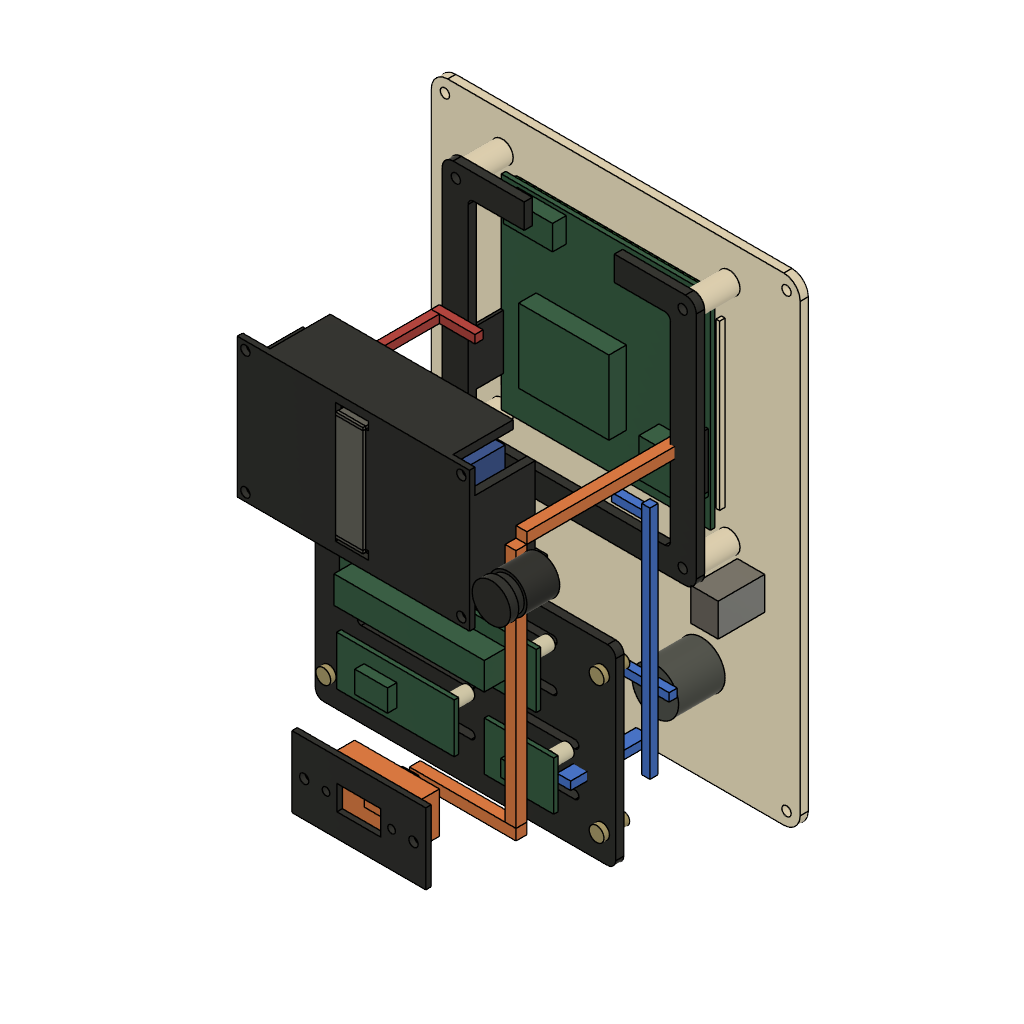
ORBIT-RevD-inspection (Autodesk Fusion 360 design; units mm, degrees)
part number: 2026-10-11-19-51-13-014
part number: 2026-10-11-19-51-13-171
part number: 2026-10-11-19-51-13-754
part number: 2026-10-11-19-51-15-998
part number: 2026-10-11-19-51-20-157
part number: 2026-10-11-19-51-22-045
part number: 2026-10-11-19-51-29-710
part number: 2026-10-11-19-51-37-269
part number: 2026-10-11-19-51-38-093
part number: 2026-10-11-19-51-39-125
part number: 2026-10-11-19-51-40-164
part number: 2026-10-11-19-51-41-218
part number: 2026-10-11-19-51-42-298
part number: 2026-10-11-19-51-44-407
part number: 2026-10-11-19-51-45-579
part number: 2026-10-11-19-51-46-216
part number: 2026-10-11-19-51-46-876
part number: 2026-10-11-19-51-47-517
part number: 2026-10-11-19-51-48-186
part number: 2026-10-11-19-51-49-445
part number: 2026-10-11-19-51-50-730
part number: 2026-10-11-19-51-51-999
part number: 2026-10-11-19-51-55-690
part number: 2026-10-11-19-52-03-764
part number: 2026-10-11-19-52-06-742
part number: 2026-10-11-19-52-09-801
part number: 2026-10-11-19-54-35-240
part number: 2026-10-11-20-27-58-250
part number: 2026-10-11-20-28-22-138
part number: 2026-10-11-20-28-23-770
part number: 2026-10-11-20-28-28-011
part number: 2026-10-11-20-28-32-254
Autodesk Fusion 360 part; units mm, degrees
(part 1 of 2)
ref_plane "WorkPlane1" through (0, 0, 0) normal (0, 0, 1) x (1, 0, 0) in component "01 Ivory front panel"
sketch "Front panel 3mm" plane through (0, 0, 0) normal (0, 0, 1) x (1, 0, 0) in component "01 Ivory front panel"
  line L0 (6, 0) -> (129, 0)
  arc A0 (129, 0) -> (135, 6) centre (129, 6) ccw
  line L1 (135, 6) -> (135, 169)
  arc A1 (135, 169) -> (129, 175) centre (129, 169) ccw
  line L2 (129, 175) -> (6, 175)
  arc A2 (6, 175) -> (0, 169) centre (6, 169) ccw
  line L3 (0, 169) -> (0, 6)
  arc A3 (0, 6) -> (6, 0) centre (6, 6) ccw
extrude "Front panel 3mm (1)" add sketch "Front panel 3mm" along normal blind 3 makes body 1 in component "01 Ivory front panel"
ref_plane "WorkPlane2" through (0, 0, 0) normal (0, 0, 1) x (1, 0, 0) in component "01 Ivory front panel"
sketch "Display aperture - provisional" plane through (0, 0, 0) normal (0, 0, 1) x (1, 0, 0) in component "01 Ivory front panel"
  line L0 (32.5, 85) -> (102.5, 85)
  arc A0 (102.5, 85) -> (103.5, 86) centre (102.5, 86) ccw
  line L1 (103.5, 86) -> (103.5, 156)
  arc A1 (103.5, 156) -> (102.5, 157) centre (102.5, 156) ccw
  line L2 (102.5, 157) -> (32.5, 157)
  arc A2 (32.5, 157) -> (31.5, 156) centre (32.5, 156) ccw
  line L3 (31.5, 156) -> (31.5, 86)
  arc A3 (31.5, 86) -> (32.5, 85) centre (32.5, 86) ccw
extrude "Display aperture - provisional (1)" cut sketch "Display aperture - provisional" along normal blind 3 bodies 1 in component "01 Ivory front panel"
ref_plane "WorkPlane3" through (0, 0, 0) normal (0, 0, 1) x (1, 0, 0) in component "01 Ivory front panel"
sketch "Encoder clearance" plane through (0, 0, 0) normal (0, 0, 1) x (1, 0, 0) in component "01 Ivory front panel"
  circle A0 centre (36, 36) radius 3.7
extrude "Encoder clearance (1)" cut sketch "Encoder clearance" along normal blind 3 bodies 1 in component "01 Ivory front panel"
ref_plane "WorkPlane4" through (0, 0, 0) normal (0, 0, 1) x (1, 0, 0) in component "01 Ivory front panel"
sketch "Potentiometer clearance" plane through (0, 0, 0) normal (0, 0, 1) x (1, 0, 0) in component "01 Ivory front panel"
  circle A0 centre (99, 36) radius 3.7
extrude "Potentiometer clearance (1)" cut sketch "Potentiometer clearance" along normal blind 3 bodies 1 in component "01 Ivory front panel"
ref_plane "WorkPlane5" through (0, 0, 0) normal (0, 0, 1) x (1, 0, 0) in component "01 Ivory front panel"
sketch "Hold toggle clearance" plane through (0, 0, 0) normal (0, 0, 1) x (1, 0, 0) in component "01 Ivory front panel"
  circle A0 centre (18, 70) radius 3.2
extrude "Hold toggle clearance (1)" cut sketch "Hold toggle clearance" along normal blind 3 bodies 1 in component "01 Ivory front panel"
ref_plane "WorkPlane6" through (0, 0, 0) normal (0, 0, 1) x (1, 0, 0) in component "01 Ivory front panel"
sketch "Grid toggle clearance" plane through (0, 0, 0) normal (0, 0, 1) x (1, 0, 0) in component "01 Ivory front panel"
  circle A0 centre (117, 70) radius 3.2
extrude "Grid toggle clearance (1)" cut sketch "Grid toggle clearance" along normal blind 3 bodies 1 in component "01 Ivory front panel"
ref_plane "WorkPlane7" through (0, 0, 0) normal (0, 0, 1) x (1, 0, 0) in component "01 Ivory front panel"
sketch "Decorative disk slot recess" plane through (0, 0, 0) normal (0, 0, 1) x (1, 0, 0) in component "01 Ivory front panel"
  line L0 (51.5, 16) -> (83.5, 16)
  arc A0 (83.5, 16) -> (84.5, 17) centre (83.5, 17) ccw
  line L1 (84.5, 17) -> (84.5, 17.4)
  arc A1 (84.5, 17.4) -> (83.5, 18.4) centre (83.5, 17.4) ccw
  line L2 (83.5, 18.4) -> (51.5, 18.4)
  arc A2 (51.5, 18.4) -> (50.5, 17.4) centre (51.5, 17.4) ccw
  line L3 (50.5, 17.4) -> (50.5, 17)
  arc A3 (50.5, 17) -> (51.5, 16) centre (51.5, 17) ccw
extrude "Decorative disk slot recess (1)" cut sketch "Decorative disk slot recess" along normal blind 0.8 bodies 1 in component "01 Ivory front panel"
ref_plane "WorkPlane8" through (0, 0, 0) normal (0, 0, 1) x (1, 0, 0) in component "01 Ivory front panel"
sketch "M3 front screw" plane through (0, 0, 0) normal (0, 0, 1) x (1, 0, 0) in component "01 Ivory front panel"
  circle A0 centre (5, 5) radius 1.7
extrude "M3 front screw (1)" cut sketch "M3 front screw" along normal blind 3 bodies 1 in component "01 Ivory front panel"
ref_plane "WorkPlane9" through (0, 0, 0) normal (0, 0, 1) x (1, 0, 0) in component "01 Ivory front panel"
sketch "M3 front screw (1)" plane through (0, 0, 0) normal (0, 0, 1) x (1, 0, 0) in component "01 Ivory front panel"
  circle A0 centre (130, 5) radius 1.7
extrude "M3 front screw (2)" cut sketch "M3 front screw (1)" along normal blind 3 bodies 1 in component "01 Ivory front panel"
ref_plane "WorkPlane10" through (0, 0, 0) normal (0, 0, 1) x (1, 0, 0) in component "01 Ivory front panel"
sketch "M3 front screw (2)" plane through (0, 0, 0) normal (0, 0, 1) x (1, 0, 0) in component "01 Ivory front panel"
  circle A0 centre (5, 170) radius 1.7
extrude "M3 front screw (3)" cut sketch "M3 front screw (2)" along normal blind 3 bodies 1 in component "01 Ivory front panel"
ref_plane "WorkPlane11" through (0, 0, 0) normal (0, 0, 1) x (1, 0, 0) in component "01 Ivory front panel"
sketch "M3 front screw (3)" plane through (0, 0, 0) normal (0, 0, 1) x (1, 0, 0) in component "01 Ivory front panel"
  circle A0 centre (130, 170) radius 1.7
extrude "M3 front screw (4)" cut sketch "M3 front screw (3)" along normal blind 3 bodies 1 in component "01 Ivory front panel"
ref_plane "WorkPlane1" through (0, 0, 3) normal (0, 0, 1) x (1, 0, 0) in component "02 Ivory shell"
sketch "Shell exterior" plane through (0, 0, 3) normal (0, 0, 1) x (1, 0, 0) in component "02 Ivory shell"
  line L0 (6, 0) -> (129, 0)
  arc A0 (129, 0) -> (135, 6) centre (129, 6) ccw
  line L1 (135, 6) -> (135, 169)
  arc A1 (135, 169) -> (129, 175) centre (129, 169) ccw
  line L2 (129, 175) -> (6, 175)
  arc A2 (6, 175) -> (0, 169) centre (6, 169) ccw
  line L3 (0, 169) -> (0, 6)
  arc A3 (0, 6) -> (6, 0) centre (6, 6) ccw
extrude "Shell exterior (1)" add sketch "Shell exterior" along normal blind 89 separate body makes body 2 in component "02 Ivory shell"
ref_plane "WorkPlane2" through (0, 0, 3) normal (0, 0, 1) x (1, 0, 0) in component "02 Ivory shell"
sketch "Open cavity 2.4mm walls" plane through (0, 0, 3) normal (0, 0, 1) x (1, 0, 0) in component "02 Ivory shell"
  line L0 (6, 2.4) -> (129, 2.4)
  arc A0 (129, 2.4) -> (132.6, 6) centre (129, 6) ccw
  line L1 (132.6, 6) -> (132.6, 169)
  arc A1 (132.6, 169) -> (129, 172.6) centre (129, 169) ccw
  line L2 (129, 172.6) -> (6, 172.6)
  arc A2 (6, 172.6) -> (2.4, 169) centre (6, 169) ccw
  line L3 (2.4, 169) -> (2.4, 6)
  arc A3 (2.4, 6) -> (6, 2.4) centre (6, 6) ccw
extrude "Open cavity 2.4mm walls (1)" cut sketch "Open cavity 2.4mm walls" along normal blind 89 bodies 2 in component "02 Ivory shell"
ref_plane "WorkPlane3" through (0, 0, 3) normal (0, 0, 1) x (1, 0, 0) in component "02 Ivory shell"
sketch "M3 corner boss" plane through (0, 0, 3) normal (0, 0, 1) x (1, 0, 0) in component "02 Ivory shell"
  circle A0 centre (5, 5) radius 4
extrude "M3 corner boss (1)" add sketch "M3 corner boss" along normal blind 8 bodies 2 in component "02 Ivory shell"
ref_plane "WorkPlane4" through (0, 0, 3) normal (0, 0, 1) x (1, 0, 0) in component "02 Ivory shell"
sketch "M3 boss bore" plane through (0, 0, 3) normal (0, 0, 1) x (1, 0, 0) in component "02 Ivory shell"
  circle A0 centre (5, 5) radius 1.7
extrude "M3 boss bore (1)" cut sketch "M3 boss bore" along normal blind 8 bodies 2 in component "02 Ivory shell"
ref_plane "WorkPlane5" through (0, 0, 84) normal (0, 0, 1) x (1, 0, 0) in component "02 Ivory shell"
sketch "M3 corner boss (1)" plane through (0, 0, 84) normal (0, 0, 1) x (1, 0, 0) in component "02 Ivory shell"
  circle A0 centre (5, 5) radius 4
extrude "M3 corner boss (2)" add sketch "M3 corner boss (1)" along normal blind 8 bodies 2 in component "02 Ivory shell"
ref_plane "WorkPlane6" through (0, 0, 84) normal (0, 0, 1) x (1, 0, 0) in component "02 Ivory shell"
sketch "M3 boss bore (1)" plane through (0, 0, 84) normal (0, 0, 1) x (1, 0, 0) in component "02 Ivory shell"
  circle A0 centre (5, 5) radius 1.7
extrude "M3 boss bore (2)" cut sketch "M3 boss bore (1)" along normal blind 8 bodies 2 in component "02 Ivory shell"
ref_plane "WorkPlane7" through (0, 0, 3) normal (0, 0, 1) x (1, 0, 0) in component "02 Ivory shell"
sketch "M3 corner boss (2)" plane through (0, 0, 3) normal (0, 0, 1) x (1, 0, 0) in component "02 Ivory shell"
  circle A0 centre (130, 5) radius 4
extrude "M3 corner boss (3)" add sketch "M3 corner boss (2)" along normal blind 8 bodies 2 in component "02 Ivory shell"
ref_plane "WorkPlane8" through (0, 0, 3) normal (0, 0, 1) x (1, 0, 0) in component "02 Ivory shell"
sketch "M3 boss bore (2)" plane through (0, 0, 3) normal (0, 0, 1) x (1, 0, 0) in component "02 Ivory shell"
  circle A0 centre (130, 5) radius 1.7
extrude "M3 boss bore (3)" cut sketch "M3 boss bore (2)" along normal blind 8 bodies 2 in component "02 Ivory shell"
ref_plane "WorkPlane9" through (0, 0, 84) normal (0, 0, 1) x (1, 0, 0) in component "02 Ivory shell"
sketch "M3 corner boss (3)" plane through (0, 0, 84) normal (0, 0, 1) x (1, 0, 0) in component "02 Ivory shell"
  circle A0 centre (130, 5) radius 4
extrude "M3 corner boss (4)" add sketch "M3 corner boss (3)" along normal blind 8 bodies 2 in component "02 Ivory shell"
ref_plane "WorkPlane10" through (0, 0, 84) normal (0, 0, 1) x (1, 0, 0) in component "02 Ivory shell"
sketch "M3 boss bore (3)" plane through (0, 0, 84) normal (0, 0, 1) x (1, 0, 0) in component "02 Ivory shell"
  circle A0 centre (130, 5) radius 1.7
extrude "M3 boss bore (4)" cut sketch "M3 boss bore (3)" along normal blind 8 bodies 2 in component "02 Ivory shell"
ref_plane "WorkPlane11" through (0, 0, 3) normal (0, 0, 1) x (1, 0, 0) in component "02 Ivory shell"
sketch "M3 corner boss (4)" plane through (0, 0, 3) normal (0, 0, 1) x (1, 0, 0) in component "02 Ivory shell"
  circle A0 centre (5, 170) radius 4
extrude "M3 corner boss (5)" add sketch "M3 corner boss (4)" along normal blind 8 bodies 2 in component "02 Ivory shell"
ref_plane "WorkPlane12" through (0, 0, 3) normal (0, 0, 1) x (1, 0, 0) in component "02 Ivory shell"
sketch "M3 boss bore (4)" plane through (0, 0, 3) normal (0, 0, 1) x (1, 0, 0) in component "02 Ivory shell"
  circle A0 centre (5, 170) radius 1.7
extrude "M3 boss bore (5)" cut sketch "M3 boss bore (4)" along normal blind 8 bodies 2 in component "02 Ivory shell"
ref_plane "WorkPlane13" through (0, 0, 84) normal (0, 0, 1) x (1, 0, 0) in component "02 Ivory shell"
sketch "M3 corner boss (5)" plane through (0, 0, 84) normal (0, 0, 1) x (1, 0, 0) in component "02 Ivory shell"
  circle A0 centre (5, 170) radius 4
extrude "M3 corner boss (6)" add sketch "M3 corner boss (5)" along normal blind 8 bodies 2 in component "02 Ivory shell"
ref_plane "WorkPlane14" through (0, 0, 84) normal (0, 0, 1) x (1, 0, 0) in component "02 Ivory shell"
sketch "M3 boss bore (5)" plane through (0, 0, 84) normal (0, 0, 1) x (1, 0, 0) in component "02 Ivory shell"
  circle A0 centre (5, 170) radius 1.7
extrude "M3 boss bore (6)" cut sketch "M3 boss bore (5)" along normal blind 8 bodies 2 in component "02 Ivory shell"
ref_plane "WorkPlane15" through (0, 0, 3) normal (0, 0, 1) x (1, 0, 0) in component "02 Ivory shell"
sketch "M3 corner boss (6)" plane through (0, 0, 3) normal (0, 0, 1) x (1, 0, 0) in component "02 Ivory shell"
  circle A0 centre (130, 170) radius 4
extrude "M3 corner boss (7)" add sketch "M3 corner boss (6)" along normal blind 8 bodies 2 in component "02 Ivory shell"
ref_plane "WorkPlane16" through (0, 0, 3) normal (0, 0, 1) x (1, 0, 0) in component "02 Ivory shell"
sketch "M3 boss bore (6)" plane through (0, 0, 3) normal (0, 0, 1) x (1, 0, 0) in component "02 Ivory shell"
  circle A0 centre (130, 170) radius 1.7
extrude "M3 boss bore (7)" cut sketch "M3 boss bore (6)" along normal blind 8 bodies 2 in component "02 Ivory shell"
ref_plane "WorkPlane17" through (0, 0, 84) normal (0, 0, 1) x (1, 0, 0) in component "02 Ivory shell"
sketch "M3 corner boss (7)" plane through (0, 0, 84) normal (0, 0, 1) x (1, 0, 0) in component "02 Ivory shell"
  circle A0 centre (130, 170) radius 4
extrude "M3 corner boss (8)" add sketch "M3 corner boss (7)" along normal blind 8 bodies 2 in component "02 Ivory shell"
ref_plane "WorkPlane18" through (0, 0, 84) normal (0, 0, 1) x (1, 0, 0) in component "02 Ivory shell"
sketch "M3 boss bore (7)" plane through (0, 0, 84) normal (0, 0, 1) x (1, 0, 0) in component "02 Ivory shell"
  circle A0 centre (130, 170) radius 1.7
extrude "M3 boss bore (8)" cut sketch "M3 boss bore (7)" along normal blind 8 bodies 2 in component "02 Ivory shell"
ref_plane "WorkPlane1" through (0, 0, 92) normal (0, 0, 1) x (1, 0, 0) in component "03 Ivory rear cover"
sketch "Rear cover" plane through (0, 0, 92) normal (0, 0, 1) x (1, 0, 0) in component "03 Ivory rear cover"
  line L0 (6, 0) -> (129, 0)
  arc A0 (129, 0) -> (135, 6) centre (129, 6) ccw
  line L1 (135, 6) -> (135, 169)
  arc A1 (135, 169) -> (129, 175) centre (129, 169) ccw
  line L2 (129, 175) -> (6, 175)
  arc A2 (6, 175) -> (0, 169) centre (6, 169) ccw
  line L3 (0, 169) -> (0, 6)
  arc A3 (0, 6) -> (6, 0) centre (6, 6) ccw
extrude "Rear cover (1)" add sketch "Rear cover" along normal blind 3 separate body makes body 3 in component "03 Ivory rear cover"
ref_plane "WorkPlane2" through (0, 0, 92) normal (0, 0, 1) x (1, 0, 0) in component "03 Ivory rear cover"
sketch "M3 rear screw" plane through (0, 0, 92) normal (0, 0, 1) x (1, 0, 0) in component "03 Ivory rear cover"
  circle A0 centre (5, 5) radius 1.7
extrude "M3 rear screw (1)" cut sketch "M3 rear screw" along normal blind 3 bodies 3 in component "03 Ivory rear cover"
ref_plane "WorkPlane3" through (0, 0, 92) normal (0, 0, 1) x (1, 0, 0) in component "03 Ivory rear cover"
sketch "M3 rear screw (1)" plane through (0, 0, 92) normal (0, 0, 1) x (1, 0, 0) in component "03 Ivory rear cover"
  circle A0 centre (130, 5) radius 1.7
extrude "M3 rear screw (2)" cut sketch "M3 rear screw (1)" along normal blind 3 bodies 3 in component "03 Ivory rear cover"
ref_plane "WorkPlane4" through (0, 0, 92) normal (0, 0, 1) x (1, 0, 0) in component "03 Ivory rear cover"
sketch "M3 rear screw (2)" plane through (0, 0, 92) normal (0, 0, 1) x (1, 0, 0) in component "03 Ivory rear cover"
  circle A0 centre (5, 170) radius 1.7
extrude "M3 rear screw (3)" cut sketch "M3 rear screw (2)" along normal blind 3 bodies 3 in component "03 Ivory rear cover"
ref_plane "WorkPlane5" through (0, 0, 92) normal (0, 0, 1) x (1, 0, 0) in component "03 Ivory rear cover"
sketch "M3 rear screw (3)" plane through (0, 0, 92) normal (0, 0, 1) x (1, 0, 0) in component "03 Ivory rear cover"
  circle A0 centre (130, 170) radius 1.7
extrude "M3 rear screw (4)" cut sketch "M3 rear screw (3)" along normal blind 3 bodies 3 in component "03 Ivory rear cover"
ref_plane "WorkPlane6" through (0, 0, 92) normal (0, 0, 1) x (1, 0, 0) in component "03 Ivory rear cover"
sketch "USB service opening - adapter required" plane through (0, 0, 92) normal (0, 0, 1) x (1, 0, 0) in component "03 Ivory rear cover"
  line L0 (52.5, 12) -> (82.5, 12)
  arc A0 (82.5, 12) -> (84.5, 14) centre (82.5, 14) ccw
  line L1 (84.5, 14) -> (84.5, 28)
  arc A1 (84.5, 28) -> (82.5, 30) centre (82.5, 28) ccw
  line L2 (82.5, 30) -> (52.5, 30)
  arc A2 (52.5, 30) -> (50.5, 28) centre (52.5, 28) ccw
  line L3 (50.5, 28) -> (50.5, 14)
  arc A3 (50.5, 14) -> (52.5, 12) centre (52.5, 14) ccw
extrude "USB service opening - adapter required (1)" cut sketch "USB service opening - adapter required" along normal blind 3 bodies 3 in component "03 Ivory rear cover"
ref_plane "WorkPlane7" through (0, 0, 92) normal (0, 0, 1) x (1, 0, 0) in component "03 Ivory rear cover"
sketch "Rear vent" plane through (0, 0, 92) normal (0, 0, 1) x (1, 0, 0) in component "03 Ivory rear cover"
  line L0 (36, 145) -> (37, 145)
  arc A0 (37, 145) -> (38, 146) centre (37, 146) ccw
  line L1 (38, 146) -> (38, 159)
  arc A1 (38, 159) -> (37, 160) centre (37, 159) ccw
  line L2 (37, 160) -> (36, 160)
  arc A2 (36, 160) -> (35, 159) centre (36, 159) ccw
  line L3 (35, 159) -> (35, 146)
  arc A3 (35, 146) -> (36, 145) centre (36, 146) ccw
extrude "Rear vent (1)" cut sketch "Rear vent" along normal blind 3 bodies 3 in component "03 Ivory rear cover"
ref_plane "WorkPlane8" through (0, 0, 92) normal (0, 0, 1) x (1, 0, 0) in component "03 Ivory rear cover"
sketch "Rear vent (1)" plane through (0, 0, 92) normal (0, 0, 1) x (1, 0, 0) in component "03 Ivory rear cover"
  line L0 (46, 145) -> (47, 145)
  arc A0 (47, 145) -> (48, 146) centre (47, 146) ccw
  line L1 (48, 146) -> (48, 159)
  arc A1 (48, 159) -> (47, 160) centre (47, 159) ccw
  line L2 (47, 160) -> (46, 160)
  arc A2 (46, 160) -> (45, 159) centre (46, 159) ccw
  line L3 (45, 159) -> (45, 146)
  arc A3 (45, 146) -> (46, 145) centre (46, 146) ccw
extrude "Rear vent (2)" cut sketch "Rear vent (1)" along normal blind 3 bodies 3 in component "03 Ivory rear cover"
ref_plane "WorkPlane9" through (0, 0, 92) normal (0, 0, 1) x (1, 0, 0) in component "03 Ivory rear cover"
sketch "Rear vent (2)" plane through (0, 0, 92) normal (0, 0, 1) x (1, 0, 0) in component "03 Ivory rear cover"
  line L0 (56, 145) -> (57, 145)
  arc A0 (57, 145) -> (58, 146) centre (57, 146) ccw
  line L1 (58, 146) -> (58, 159)
  arc A1 (58, 159) -> (57, 160) centre (57, 159) ccw
  line L2 (57, 160) -> (56, 160)
  arc A2 (56, 160) -> (55, 159) centre (56, 159) ccw
  line L3 (55, 159) -> (55, 146)
  arc A3 (55, 146) -> (56, 145) centre (56, 146) ccw
extrude "Rear vent (3)" cut sketch "Rear vent (2)" along normal blind 3 bodies 3 in component "03 Ivory rear cover"
ref_plane "WorkPlane10" through (0, 0, 92) normal (0, 0, 1) x (1, 0, 0) in component "03 Ivory rear cover"
sketch "Rear vent (3)" plane through (0, 0, 92) normal (0, 0, 1) x (1, 0, 0) in component "03 Ivory rear cover"
  line L0 (66, 145) -> (67, 145)
  arc A0 (67, 145) -> (68, 146) centre (67, 146) ccw
  line L1 (68, 146) -> (68, 159)
  arc A1 (68, 159) -> (67, 160) centre (67, 159) ccw
  line L2 (67, 160) -> (66, 160)
  arc A2 (66, 160) -> (65, 159) centre (66, 159) ccw
  line L3 (65, 159) -> (65, 146)
  arc A3 (65, 146) -> (66, 145) centre (66, 146) ccw
extrude "Rear vent (4)" cut sketch "Rear vent (3)" along normal blind 3 bodies 3 in component "03 Ivory rear cover"
ref_plane "WorkPlane11" through (0, 0, 92) normal (0, 0, 1) x (1, 0, 0) in component "03 Ivory rear cover"
sketch "Rear vent (4)" plane through (0, 0, 92) normal (0, 0, 1) x (1, 0, 0) in component "03 Ivory rear cover"
  line L0 (76, 145) -> (77, 145)
  arc A0 (77, 145) -> (78, 146) centre (77, 146) ccw
  line L1 (78, 146) -> (78, 159)
  arc A1 (78, 159) -> (77, 160) centre (77, 159) ccw
  line L2 (77, 160) -> (76, 160)
  arc A2 (76, 160) -> (75, 159) centre (76, 159) ccw
  line L3 (75, 159) -> (75, 146)
  arc A3 (75, 146) -> (76, 145) centre (76, 146) ccw
extrude "Rear vent (5)" cut sketch "Rear vent (4)" along normal blind 3 bodies 3 in component "03 Ivory rear cover"
ref_plane "WorkPlane12" through (0, 0, 92) normal (0, 0, 1) x (1, 0, 0) in component "03 Ivory rear cover"
sketch "Rear vent (5)" plane through (0, 0, 92) normal (0, 0, 1) x (1, 0, 0) in component "03 Ivory rear cover"
  line L0 (86, 145) -> (87, 145)
  arc A0 (87, 145) -> (88, 146) centre (87, 146) ccw
  line L1 (88, 146) -> (88, 159)
  arc A1 (88, 159) -> (87, 160) centre (87, 159) ccw
  line L2 (87, 160) -> (86, 160)
  arc A2 (86, 160) -> (85, 159) centre (86, 159) ccw
  line L3 (85, 159) -> (85, 146)
  arc A3 (85, 146) -> (86, 145) centre (86, 146) ccw
extrude "Rear vent (6)" cut sketch "Rear vent (5)" along normal blind 3 bodies 3 in component "03 Ivory rear cover"
ref_plane "WorkPlane13" through (0, 0, 92) normal (0, 0, 1) x (1, 0, 0) in component "03 Ivory rear cover"
sketch "Rear vent (6)" plane through (0, 0, 92) normal (0, 0, 1) x (1, 0, 0) in component "03 Ivory rear cover"
  line L0 (96, 145) -> (97, 145)
  arc A0 (97, 145) -> (98, 146) centre (97, 146) ccw
  line L1 (98, 146) -> (98, 159)
  arc A1 (98, 159) -> (97, 160) centre (97, 159) ccw
  line L2 (97, 160) -> (96, 160)
  arc A2 (96, 160) -> (95, 159) centre (96, 159) ccw
  line L3 (95, 159) -> (95, 146)
  arc A3 (95, 146) -> (96, 145) centre (96, 146) ccw
extrude "Rear vent (7)" cut sketch "Rear vent (6)" along normal blind 3 bodies 3 in component "03 Ivory rear cover"
ref_plane "WorkPlane14" through (0, 0, 92) normal (0, 0, 1) x (1, 0, 0) in component "03 Ivory rear cover"
sketch "Rear vent (7)" plane through (0, 0, 92) normal (0, 0, 1) x (1, 0, 0) in component "03 Ivory rear cover"
  line L0 (106, 145) -> (107, 145)
  arc A0 (107, 145) -> (108, 146) centre (107, 146) ccw
  line L1 (108, 146) -> (108, 159)
  arc A1 (108, 159) -> (107, 160) centre (107, 159) ccw
  line L2 (107, 160) -> (106, 160)
  arc A2 (106, 160) -> (105, 159) centre (106, 159) ccw
  line L3 (105, 159) -> (105, 146)
  arc A3 (105, 146) -> (106, 145) centre (106, 146) ccw
extrude "Rear vent (8)" cut sketch "Rear vent (7)" along normal blind 3 bodies 3 in component "03 Ivory rear cover"
ref_plane "WorkPlane1" through (0, 0, -2) normal (0, 0, 1) x (1, 0, 0) in component "04 Charcoal bezel"
sketch "Inset display bezel" plane through (0, 0, -2) normal (0, 0, 1) x (1, 0, 0) in component "04 Charcoal bezel"
  line L0 (31.5, 81) -> (103.5, 81)
  arc A0 (103.5, 81) -> (107.5, 85) centre (103.5, 85) ccw
  line L1 (107.5, 85) -> (107.5, 157)
  arc A1 (107.5, 157) -> (103.5, 161) centre (103.5, 157) ccw
  line L2 (103.5, 161) -> (31.5, 161)
  arc A2 (31.5, 161) -> (27.5, 157) centre (31.5, 157) ccw
  line L3 (27.5, 157) -> (27.5, 85)
  arc A3 (27.5, 85) -> (31.5, 81) centre (31.5, 85) ccw
extrude "Inset display bezel (1)" add sketch "Inset display bezel" along normal blind 2 separate body makes body 4 in component "04 Charcoal bezel"
ref_plane "WorkPlane2" through (0, 0, -2) normal (0, 0, 1) x (1, 0, 0) in component "04 Charcoal bezel"
sketch "Bezel view opening" plane through (0, 0, -2) normal (0, 0, 1) x (1, 0, 0) in component "04 Charcoal bezel"
  line L0 (32.5, 85) -> (102.5, 85)
  arc A0 (102.5, 85) -> (103.5, 86) centre (102.5, 86) ccw
  line L1 (103.5, 86) -> (103.5, 156)
  arc A1 (103.5, 156) -> (102.5, 157) centre (102.5, 156) ccw
  line L2 (102.5, 157) -> (32.5, 157)
  arc A2 (32.5, 157) -> (31.5, 156) centre (32.5, 156) ccw
  line L3 (31.5, 156) -> (31.5, 86)
  arc A3 (31.5, 86) -> (32.5, 85) centre (32.5, 86) ccw
extrude "Bezel view opening (1)" cut sketch "Bezel view opening" along normal blind 2 bodies 4 in component "04 Charcoal bezel"
ref_plane "WorkPlane3" through (0, 0, 0) normal (0, 0, 1) x (1, 0, 0) in component "04 Charcoal bezel"
sketch "Bezel locating peg" plane through (0, 0, 0) normal (0, 0, 1) x (1, 0, 0) in component "04 Charcoal bezel"
  circle A0 centre (29.5, 83) radius 0.9
extrude "Bezel locating peg (1)" add sketch "Bezel locating peg" along normal blind 2 bodies 4 in component "04 Charcoal bezel"
ref_plane "WorkPlane12" through (0, 0, 0) normal (0, 0, 1) x (1, 0, 0) in component "01 Ivory front panel"
sketch "Bezel locating socket" plane through (0, 0, 0) normal (0, 0, 1) x (1, 0, 0) in component "01 Ivory front panel"
  circle A0 centre (29.5, 83) radius 1.1
extrude "Bezel locating socket (1)" cut sketch "Bezel locating socket" along normal blind 2.2 bodies 1 in component "01 Ivory front panel"
extrude "Extrude4" cut sketch "Bezel locating socket" along normal blind 2.2 bodies 4 in component "04 Charcoal bezel"
ref_plane "WorkPlane4" through (0, 0, 0) normal (0, 0, 1) x (1, 0, 0) in component "04 Charcoal bezel"
sketch "Bezel locating peg (1)" plane through (0, 0, 0) normal (0, 0, 1) x (1, 0, 0) in component "04 Charcoal bezel"
  circle A0 centre (105.5, 159) radius 0.9
extrude "Bezel locating peg (2)" add sketch "Bezel locating peg (1)" along normal blind 2 bodies 4 in component "04 Charcoal bezel"
ref_plane "WorkPlane13" through (0, 0, 0) normal (0, 0, 1) x (1, 0, 0) in component "01 Ivory front panel"
sketch "Bezel locating socket (1)" plane through (0, 0, 0) normal (0, 0, 1) x (1, 0, 0) in component "01 Ivory front panel"
  circle A0 centre (105.5, 159) radius 1.1
extrude "Bezel locating socket (2)" cut sketch "Bezel locating socket (1)" along normal blind 2.2 bodies 1 in component "01 Ivory front panel"
extrude "Extrude6" cut sketch "Bezel locating socket (1)" along normal blind 2.2 bodies 4 in component "04 Charcoal bezel"
ref_plane "WorkPlane1" through (0, 0, 55) normal (0, 0, 1) x (1, 0, 0) in component "05 Internal removable control tray"
sketch "Tray installed below screen" plane through (0, 0, 55) normal (0, 0, 1) x (1, 0, 0) in component "05 Internal removable control tray"
  line L0 (15.5, 10) -> (119.5, 10)
  arc A0 (119.5, 10) -> (122.5, 13) centre (119.5, 13) ccw
  line L1 (122.5, 13) -> (122.5, 77)
  arc A1 (122.5, 77) -> (119.5, 80) centre (119.5, 77) ccw
  line L2 (119.5, 80) -> (15.5, 80)
  arc A2 (15.5, 80) -> (12.5, 77) centre (15.5, 77) ccw
  line L3 (12.5, 77) -> (12.5, 13)
  arc A3 (12.5, 13) -> (15.5, 10) centre (15.5, 13) ccw
extrude "Tray installed below screen (1)" add sketch "Tray installed below screen" along normal blind 3 separate body makes body 5 in component "05 Internal removable control tray"
ref_plane "WorkPlane2" through (0, 0, 55) normal (0, 0, 1) x (1, 0, 0) in component "05 Internal removable control tray"
sketch "M3 tray fixing" plane through (0, 0, 55) normal (0, 0, 1) x (1, 0, 0) in component "05 Internal removable control tray"
  circle A0 centre (17.5, 20) radius 1.7
extrude "M3 tray fixing (1)" cut sketch "M3 tray fixing" along normal blind 3 bodies 5 in component "05 Internal removable control tray"
ref_plane "WorkPlane19" through (0, 0, 48) normal (0, 0, 1) x (1, 0, 0) in component "02 Ivory shell"
sketch "Tray support ledge" plane through (0, 0, 48) normal (0, 0, 1) x (1, 0, 0) in component "02 Ivory shell"
  line L0 (1, 14) -> (24, 14)
  line L1 (24, 14) -> (24, 26)
  line L2 (24, 26) -> (1, 26)
  line L3 (1, 26) -> (1, 14)
extrude "Tray support ledge (1)" add sketch "Tray support ledge" along normal blind 7 bodies 2 in component "02 Ivory shell"
ref_plane "WorkPlane20" through (0, 0, 50) normal (0, 0, 1) x (1, 0, 0) in component "02 Ivory shell"
sketch "M3 heat insert pilot - calibrate" plane through (0, 0, 50) normal (0, 0, 1) x (1, 0, 0) in component "02 Ivory shell"
  circle A0 centre (17.5, 20) radius 2.2
extrude "M3 heat insert pilot - calibrate (1)" cut sketch "M3 heat insert pilot - calibrate" along normal blind 5 bodies 2 in component "02 Ivory shell"
ref_plane "WorkPlane3" through (0, 0, 55) normal (0, 0, 1) x (1, 0, 0) in component "05 Internal removable control tray"
sketch "M3 tray fixing (1)" plane through (0, 0, 55) normal (0, 0, 1) x (1, 0, 0) in component "05 Internal removable control tray"
  circle A0 centre (17.5, 70) radius 1.7
extrude "M3 tray fixing (2)" cut sketch "M3 tray fixing (1)" along normal blind 3 bodies 5 in component "05 Internal removable control tray"
ref_plane "WorkPlane21" through (0, 0, 48) normal (0, 0, 1) x (1, 0, 0) in component "02 Ivory shell"
sketch "Tray support ledge (1)" plane through (0, 0, 48) normal (0, 0, 1) x (1, 0, 0) in component "02 Ivory shell"
  line L0 (1, 64) -> (24, 64)
  line L1 (24, 64) -> (24, 76)
  line L2 (24, 76) -> (1, 76)
  line L3 (1, 76) -> (1, 64)
extrude "Tray support ledge (2)" add sketch "Tray support ledge (1)" along normal blind 7 bodies 2 in component "02 Ivory shell"
ref_plane "WorkPlane22" through (0, 0, 50) normal (0, 0, 1) x (1, 0, 0) in component "02 Ivory shell"
sketch "M3 heat insert pilot - calibrate (1)" plane through (0, 0, 50) normal (0, 0, 1) x (1, 0, 0) in component "02 Ivory shell"
  circle A0 centre (17.5, 70) radius 2.2
extrude "M3 heat insert pilot - calibrate (2)" cut sketch "M3 heat insert pilot - calibrate (1)" along normal blind 5 bodies 2 in component "02 Ivory shell"
ref_plane "WorkPlane4" through (0, 0, 55) normal (0, 0, 1) x (1, 0, 0) in component "05 Internal removable control tray"
sketch "M3 tray fixing (2)" plane through (0, 0, 55) normal (0, 0, 1) x (1, 0, 0) in component "05 Internal removable control tray"
  circle A0 centre (117.5, 20) radius 1.7
extrude "M3 tray fixing (3)" cut sketch "M3 tray fixing (2)" along normal blind 3 bodies 5 in component "05 Internal removable control tray"
ref_plane "WorkPlane23" through (0, 0, 48) normal (0, 0, 1) x (1, 0, 0) in component "02 Ivory shell"
sketch "Tray support ledge (2)" plane through (0, 0, 48) normal (0, 0, 1) x (1, 0, 0) in component "02 Ivory shell"
  line L0 (111, 14) -> (134, 14)
  line L1 (134, 14) -> (134, 26)
  line L2 (134, 26) -> (111, 26)
  line L3 (111, 26) -> (111, 14)
extrude "Tray support ledge (3)" add sketch "Tray support ledge (2)" along normal blind 7 bodies 2 in component "02 Ivory shell"
ref_plane "WorkPlane24" through (0, 0, 50) normal (0, 0, 1) x (1, 0, 0) in component "02 Ivory shell"
sketch "M3 heat insert pilot - calibrate (2)" plane through (0, 0, 50) normal (0, 0, 1) x (1, 0, 0) in component "02 Ivory shell"
  circle A0 centre (117.5, 20) radius 2.2
extrude "M3 heat insert pilot - calibrate (3)" cut sketch "M3 heat insert pilot - calibrate (2)" along normal blind 5 bodies 2 in component "02 Ivory shell"
ref_plane "WorkPlane5" through (0, 0, 55) normal (0, 0, 1) x (1, 0, 0) in component "05 Internal removable control tray"
sketch "M3 tray fixing (3)" plane through (0, 0, 55) normal (0, 0, 1) x (1, 0, 0) in component "05 Internal removable control tray"
  circle A0 centre (117.5, 70) radius 1.7
extrude "M3 tray fixing (4)" cut sketch "M3 tray fixing (3)" along normal blind 3 bodies 5 in component "05 Internal removable control tray"
ref_plane "WorkPlane25" through (0, 0, 48) normal (0, 0, 1) x (1, 0, 0) in component "02 Ivory shell"
sketch "Tray support ledge (3)" plane through (0, 0, 48) normal (0, 0, 1) x (1, 0, 0) in component "02 Ivory shell"
  line L0 (111, 64) -> (134, 64)
  line L1 (134, 64) -> (134, 76)
  line L2 (134, 76) -> (111, 76)
  line L3 (111, 76) -> (111, 64)
extrude "Tray support ledge (4)" add sketch "Tray support ledge (3)" along normal blind 7 bodies 2 in component "02 Ivory shell"
ref_plane "WorkPlane26" through (0, 0, 50) normal (0, 0, 1) x (1, 0, 0) in component "02 Ivory shell"
sketch "M3 heat insert pilot - calibrate (3)" plane through (0, 0, 50) normal (0, 0, 1) x (1, 0, 0) in component "02 Ivory shell"
  circle A0 centre (117.5, 70) radius 2.2
extrude "M3 heat insert pilot - calibrate (4)" cut sketch "M3 heat insert pilot - calibrate (3)" along normal blind 5 bodies 2 in component "02 Ivory shell"
ref_plane "WorkPlane6" through (0, 0, 55) normal (0, 0, 1) x (1, 0, 0) in component "05 Internal removable control tray"
sketch "Adjustable breakout fixing slot" plane through (0, 0, 55) normal (0, 0, 1) x (1, 0, 0) in component "05 Internal removable control tray"
  line L0 (29.4, 25) -> (69.6, 25)
  arc A0 (69.6, 25) -> (71, 26.4) centre (69.6, 26.4) ccw
  line L1 (71, 26.4) -> (71, 26.6)
  arc A1 (71, 26.6) -> (69.6, 28) centre (69.6, 26.6) ccw
  line L2 (69.6, 28) -> (29.4, 28)
  arc A2 (29.4, 28) -> (28, 26.6) centre (29.4, 26.6) ccw
  line L3 (28, 26.6) -> (28, 26.4)
  arc A3 (28, 26.4) -> (29.4, 25) centre (29.4, 26.4) ccw
extrude "Adjustable breakout fixing slot (1)" cut sketch "Adjustable breakout fixing slot" along normal blind 3 bodies 5 in component "05 Internal removable control tray"
ref_plane "WorkPlane7" through (0, 0, 55) normal (0, 0, 1) x (1, 0, 0) in component "05 Internal removable control tray"
sketch "Adjustable breakout fixing slot (1)" plane through (0, 0, 55) normal (0, 0, 1) x (1, 0, 0) in component "05 Internal removable control tray"
  line L0 (29.4, 41) -> (69.6, 41)
  arc A0 (69.6, 41) -> (71, 42.4) centre (69.6, 42.4) ccw
  line L1 (71, 42.4) -> (71, 42.6)
  arc A1 (71, 42.6) -> (69.6, 44) centre (69.6, 42.6) ccw
  line L2 (69.6, 44) -> (29.4, 44)
  arc A2 (29.4, 44) -> (28, 42.6) centre (29.4, 42.6) ccw
  line L3 (28, 42.6) -> (28, 42.4)
  arc A3 (28, 42.4) -> (29.4, 41) centre (29.4, 42.4) ccw
extrude "Adjustable breakout fixing slot (2)" cut sketch "Adjustable breakout fixing slot (1)" along normal blind 3 bodies 5 in component "05 Internal removable control tray"
ref_plane "WorkPlane8" through (0, 0, 55) normal (0, 0, 1) x (1, 0, 0) in component "05 Internal removable control tray"
sketch "Adjustable breakout fixing slot (2)" plane through (0, 0, 55) normal (0, 0, 1) x (1, 0, 0) in component "05 Internal removable control tray"
  line L0 (83.4, 25) -> (107.6, 25)
  arc A0 (107.6, 25) -> (109, 26.4) centre (107.6, 26.4) ccw
  line L1 (109, 26.4) -> (109, 26.6)
  arc A1 (109, 26.6) -> (107.6, 28) centre (107.6, 26.6) ccw
  line L2 (107.6, 28) -> (83.4, 28)
  arc A2 (83.4, 28) -> (82, 26.6) centre (83.4, 26.6) ccw
  line L3 (82, 26.6) -> (82, 26.4)
  arc A3 (82, 26.4) -> (83.4, 25) centre (83.4, 26.4) ccw
extrude "Adjustable breakout fixing slot (3)" cut sketch "Adjustable breakout fixing slot (2)" along normal blind 3 bodies 5 in component "05 Internal removable control tray"
ref_plane "WorkPlane9" through (0, 0, 55) normal (0, 0, 1) x (1, 0, 0) in component "05 Internal removable control tray"
sketch "Adjustable breakout fixing slot (3)" plane through (0, 0, 55) normal (0, 0, 1) x (1, 0, 0) in component "05 Internal removable control tray"
  line L0 (83.4, 41) -> (107.6, 41)
  arc A0 (107.6, 41) -> (109, 42.4) centre (107.6, 42.4) ccw
  line L1 (109, 42.4) -> (109, 42.6)
  arc A1 (109, 42.6) -> (107.6, 44) centre (107.6, 42.6) ccw
  line L2 (107.6, 44) -> (83.4, 44)
  arc A2 (83.4, 44) -> (82, 42.6) centre (83.4, 42.6) ccw
  line L3 (82, 42.6) -> (82, 42.4)
  arc A3 (82, 42.4) -> (83.4, 41) centre (83.4, 42.4) ccw
extrude "Adjustable breakout fixing slot (4)" cut sketch "Adjustable breakout fixing slot (3)" along normal blind 3 bodies 5 in component "05 Internal removable control tray"
ref_plane "WorkPlane10" through (0, 0, 55) normal (0, 0, 1) x (1, 0, 0) in component "05 Internal removable control tray"
sketch "Adjustable breakout fixing slot (4)" plane through (0, 0, 55) normal (0, 0, 1) x (1, 0, 0) in component "05 Internal removable control tray"
  line L0 (30.4, 54) -> (99.6, 54)
  arc A0 (99.6, 54) -> (101, 55.4) centre (99.6, 55.4) ccw
  line L1 (101, 55.4) -> (101, 55.6)
  arc A1 (101, 55.6) -> (99.6, 57) centre (99.6, 55.6) ccw
  line L2 (99.6, 57) -> (30.4, 57)
  arc A2 (30.4, 57) -> (29, 55.6) centre (30.4, 55.6) ccw
  line L3 (29, 55.6) -> (29, 55.4)
  arc A3 (29, 55.4) -> (30.4, 54) centre (30.4, 55.4) ccw
extrude "Adjustable breakout fixing slot (5)" cut sketch "Adjustable breakout fixing slot (4)" along normal blind 3 bodies 5 in component "05 Internal removable control tray"
ref_plane "WorkPlane11" through (0, 0, 55) normal (0, 0, 1) x (1, 0, 0) in component "05 Internal removable control tray"
sketch "Adjustable breakout fixing slot (5)" plane through (0, 0, 55) normal (0, 0, 1) x (1, 0, 0) in component "05 Internal removable control tray"
  line L0 (30.4, 70) -> (99.6, 70)
  arc A0 (99.6, 70) -> (101, 71.4) centre (99.6, 71.4) ccw
  line L1 (101, 71.4) -> (101, 71.6)
  arc A1 (101, 71.6) -> (99.6, 73) centre (99.6, 71.6) ccw
  line L2 (99.6, 73) -> (30.4, 73)
  arc A2 (30.4, 73) -> (29, 71.6) centre (30.4, 71.6) ccw
  line L3 (29, 71.6) -> (29, 71.4)
  arc A3 (29, 71.4) -> (30.4, 70) centre (30.4, 71.4) ccw
extrude "Adjustable breakout fixing slot (6)" cut sketch "Adjustable breakout fixing slot (5)" along normal blind 3 bodies 5 in component "05 Internal removable control tray"
ref_plane "WorkPlane1" through (0, 0, 17) normal (0, 0, 1) x (1, 0, 0) in component "06 Display rear retainer - fit prototype"
sketch "Display retaining frame" plane through (0, 0, 17) normal (0, 0, 1) x (1, 0, 0) in component "06 Display rear retainer - fit prototype"
  line L0 (25, 75) -> (110, 75)
  arc A0 (110, 75) -> (114, 79) centre (110, 79) ccw
  line L1 (114, 79) -> (114, 163)
  arc A1 (114, 163) -> (110, 167) centre (110, 163) ccw
  line L2 (110, 167) -> (25, 167)
  arc A2 (25, 167) -> (21, 163) centre (25, 163) ccw
  line L3 (21, 163) -> (21, 79)
  arc A3 (21, 79) -> (25, 75) centre (25, 79) ccw
extrude "Display retaining frame (1)" add sketch "Display retaining frame" along normal blind 3 separate body makes body 6 in component "06 Display rear retainer - fit prototype"
ref_plane "WorkPlane2" through (0, 0, 17) normal (0, 0, 1) x (1, 0, 0) in component "06 Display rear retainer - fit prototype"
sketch "Rear service window" plane through (0, 0, 17) normal (0, 0, 1) x (1, 0, 0) in component "06 Display rear retainer - fit prototype"
  line L0 (32.5, 84) -> (102.5, 84)
  arc A0 (102.5, 84) -> (104.5, 86) centre (102.5, 86) ccw
  line L1 (104.5, 86) -> (104.5, 156)
  arc A1 (104.5, 156) -> (102.5, 158) centre (102.5, 156) ccw
  line L2 (102.5, 158) -> (32.5, 158)
  arc A2 (32.5, 158) -> (30.5, 156) centre (32.5, 156) ccw
  line L3 (30.5, 156) -> (30.5, 86)
  arc A3 (30.5, 86) -> (32.5, 84) centre (32.5, 86) ccw
extrude "Rear service window (1)" cut sketch "Rear service window" along normal blind 3 bodies 6 in component "06 Display rear retainer - fit prototype"
ref_plane "WorkPlane3" through (0, 0, 17) normal (0, 0, 1) x (1, 0, 0) in component "06 Display rear retainer - fit prototype"
sketch "Antenna and cable relief" plane through (0, 0, 17) normal (0, 0, 1) x (1, 0, 0) in component "06 Display rear retainer - fit prototype"
  line L0 (51, 158) -> (84, 158)
  line L1 (84, 158) -> (84, 167)
  line L2 (84, 167) -> (51, 167)
  line L3 (51, 167) -> (51, 158)
extrude "Antenna and cable relief (1)" cut sketch "Antenna and cable relief" along normal blind 3 bodies 6 in component "06 Display rear retainer - fit prototype"
ref_plane "WorkPlane4" through (0, 0, 17) normal (0, 0, 1) x (1, 0, 0) in component "06 Display rear retainer - fit prototype"
sketch "M3 retainer fixing" plane through (0, 0, 17) normal (0, 0, 1) x (1, 0, 0) in component "06 Display rear retainer - fit prototype"
  circle A0 centre (26, 80) radius 1.7
extrude "M3 retainer fixing (1)" cut sketch "M3 retainer fixing" along normal blind 3 bodies 6 in component "06 Display rear retainer - fit prototype"
ref_plane "WorkPlane14" through (0, 0, 3) normal (0, 0, 1) x (1, 0, 0) in component "01 Ivory front panel"
sketch "Display retainer stand off" plane through (0, 0, 3) normal (0, 0, 1) x (1, 0, 0) in component "01 Ivory front panel"
  circle A0 centre (26, 80) radius 4
extrude "Display retainer stand off (1)" add sketch "Display retainer stand off" along normal blind 14 bodies 1 in component "01 Ivory front panel"
ref_plane "WorkPlane15" through (0, 0, 12) normal (0, 0, 1) x (1, 0, 0) in component "01 Ivory front panel"
sketch "M3 heat insert pilot - calibrate (4)" plane through (0, 0, 12) normal (0, 0, 1) x (1, 0, 0) in component "01 Ivory front panel"
  circle A0 centre (26, 80) radius 2.2
extrude "M3 heat insert pilot - calibrate (1)'" cut sketch "M3 heat insert pilot - calibrate (4)" along normal blind 5 bodies 1 in component "01 Ivory front panel"
ref_plane "WorkPlane5" through (0, 0, 17) normal (0, 0, 1) x (1, 0, 0) in component "06 Display rear retainer - fit prototype"
sketch "M3 retainer fixing (1)" plane through (0, 0, 17) normal (0, 0, 1) x (1, 0, 0) in component "06 Display rear retainer - fit prototype"
  circle A0 centre (26, 162) radius 1.7
extrude "M3 retainer fixing (2)" cut sketch "M3 retainer fixing (1)" along normal blind 3 bodies 6 in component "06 Display rear retainer - fit prototype"
ref_plane "WorkPlane16" through (0, 0, 3) normal (0, 0, 1) x (1, 0, 0) in component "01 Ivory front panel"
sketch "Display retainer stand off (1)" plane through (0, 0, 3) normal (0, 0, 1) x (1, 0, 0) in component "01 Ivory front panel"
  circle A0 centre (26, 162) radius 4
extrude "Display retainer stand off (2)" add sketch "Display retainer stand off (1)" along normal blind 14 bodies 1 in component "01 Ivory front panel"
ref_plane "WorkPlane17" through (0, 0, 12) normal (0, 0, 1) x (1, 0, 0) in component "01 Ivory front panel"
sketch "M3 heat insert pilot - calibrate (1) (2)" plane through (0, 0, 12) normal (0, 0, 1) x (1, 0, 0) in component "01 Ivory front panel"
  circle A0 centre (26, 162) radius 2.2
extrude "M3 heat insert pilot - calibrate (2)'" cut sketch "M3 heat insert pilot - calibrate (1) (2)" along normal blind 5 bodies 1 in component "01 Ivory front panel"
ref_plane "WorkPlane6" through (0, 0, 17) normal (0, 0, 1) x (1, 0, 0) in component "06 Display rear retainer - fit prototype"
sketch "M3 retainer fixing (2)" plane through (0, 0, 17) normal (0, 0, 1) x (1, 0, 0) in component "06 Display rear retainer - fit prototype"
  circle A0 centre (109, 80) radius 1.7
extrude "M3 retainer fixing (3)" cut sketch "M3 retainer fixing (2)" along normal blind 3 bodies 6 in component "06 Display rear retainer - fit prototype"
ref_plane "WorkPlane18" through (0, 0, 3) normal (0, 0, 1) x (1, 0, 0) in component "01 Ivory front panel"
sketch "Display retainer stand off (2)" plane through (0, 0, 3) normal (0, 0, 1) x (1, 0, 0) in component "01 Ivory front panel"
  circle A0 centre (109, 80) radius 4
extrude "Display retainer stand off (3)" add sketch "Display retainer stand off (2)" along normal blind 14 bodies 1 in component "01 Ivory front panel"
ref_plane "WorkPlane19" through (0, 0, 12) normal (0, 0, 1) x (1, 0, 0) in component "01 Ivory front panel"
sketch "M3 heat insert pilot - calibrate (2) (2)" plane through (0, 0, 12) normal (0, 0, 1) x (1, 0, 0) in component "01 Ivory front panel"
  circle A0 centre (109, 80) radius 2.2
extrude "M3 heat insert pilot - calibrate (3)'" cut sketch "M3 heat insert pilot - calibrate (2) (2)" along normal blind 5 bodies 1 in component "01 Ivory front panel"
ref_plane "WorkPlane7" through (0, 0, 17) normal (0, 0, 1) x (1, 0, 0) in component "06 Display rear retainer - fit prototype"
sketch "M3 retainer fixing (3)" plane through (0, 0, 17) normal (0, 0, 1) x (1, 0, 0) in component "06 Display rear retainer - fit prototype"
  circle A0 centre (109, 162) radius 1.7
extrude "M3 retainer fixing (4)" cut sketch "M3 retainer fixing (3)" along normal blind 3 bodies 6 in component "06 Display rear retainer - fit prototype"
ref_plane "WorkPlane20" through (0, 0, 3) normal (0, 0, 1) x (1, 0, 0) in component "01 Ivory front panel"
sketch "Display retainer stand off (3)" plane through (0, 0, 3) normal (0, 0, 1) x (1, 0, 0) in component "01 Ivory front panel"
  circle A0 centre (109, 162) radius 4
extrude "Display retainer stand off (4)" add sketch "Display retainer stand off (3)" along normal blind 14 bodies 1 in component "01 Ivory front panel"
ref_plane "WorkPlane21" through (0, 0, 12) normal (0, 0, 1) x (1, 0, 0) in component "01 Ivory front panel"
sketch "M3 heat insert pilot - calibrate (3) (2)" plane through (0, 0, 12) normal (0, 0, 1) x (1, 0, 0) in component "01 Ivory front panel"
  circle A0 centre (109, 162) radius 2.2
extrude "M3 heat insert pilot - calibrate (4)'" cut sketch "M3 heat insert pilot - calibrate (3) (2)" along normal blind 5 bodies 1 in component "01 Ivory front panel"
ref_plane "WorkPlane22" through (0, 0, 3) normal (0, 0, 1) x (1, 0, 0) in component "01 Ivory front panel"
sketch "Display side support" plane through (0, 0, 3) normal (0, 0, 1) x (1, 0, 0) in component "01 Ivory front panel"
  line L0 (27.6, 90) -> (28.9, 90)
  line L1 (28.9, 90) -> (28.9, 150)
  line L2 (28.9, 150) -> (27.6, 150)
  line L3 (27.6, 150) -> (27.6, 90)
extrude "Display side support (1)" add sketch "Display side support" along normal blind 2 bodies 1 in component "01 Ivory front panel"
ref_plane "WorkPlane23" through (0, 0, 3) normal (0, 0, 1) x (1, 0, 0) in component "01 Ivory front panel"
sketch "Display side support (1)" plane through (0, 0, 3) normal (0, 0, 1) x (1, 0, 0) in component "01 Ivory front panel"
  line L0 (106.2, 90) -> (107.5, 90)
  line L1 (107.5, 90) -> (107.5, 150)
  line L2 (107.5, 150) -> (106.2, 150)
  line L3 (106.2, 150) -> (106.2, 90)
extrude "Display side support (2)" add sketch "Display side support (1)" along normal blind 2 bodies 1 in component "01 Ivory front panel"
ref_plane "WorkPlane1" through (0, 0, 3.6) normal (0, 0, 1) x (1, 0, 0) in component "REF Green TFT visible area"
sketch "Green screen proxy" plane through (0, 0, 3.6) normal (0, 0, 1) x (1, 0, 0) in component "REF Green TFT visible area"
  line L0 (32, 84.5) -> (103, 84.5)
  arc A0 (103, 84.5) -> (104, 85.5) centre (103, 85.5) ccw
  line L1 (104, 85.5) -> (104, 156.5)
  arc A1 (104, 156.5) -> (103, 157.5) centre (103, 156.5) ccw
  line L2 (103, 157.5) -> (32, 157.5)
  arc A2 (32, 157.5) -> (31, 156.5) centre (32, 156.5) ccw
  line L3 (31, 156.5) -> (31, 85.5)
  arc A3 (31, 85.5) -> (32, 84.5) centre (32, 85.5) ccw
extrude "Green screen proxy (1)" add sketch "Green screen proxy" along normal blind 1 separate body makes body 7 in component "REF Green TFT visible area"
ref_plane "WorkPlane1" through (0, 0, -16) normal (0, 0, 1) x (1, 0, 0) in component "REF Select knob"
sketch "Purchased knob envelope" plane through (0, 0, -16) normal (0, 0, 1) x (1, 0, 0) in component "REF Select knob"
  circle A0 centre (36, 36) radius 11
extrude "Purchased knob envelope (1)" add sketch "Purchased knob envelope" along normal blind 13 separate body makes body 8 in component "REF Select knob"
ref_plane "WorkPlane2" through (0, 0, -16.1) normal (0, 0, 1) x (1, 0, 0) in component "REF Select knob"
sketch "Pointer mark" plane through (0, 0, -16.1) normal (0, 0, 1) x (1, 0, 0) in component "REF Select knob"
  line L0 (35.3, 44) -> (36.7, 44)
  line L1 (36.7, 44) -> (36.7, 46.5)
  line L2 (36.7, 46.5) -> (35.3, 46.5)
  line L3 (35.3, 46.5) -> (35.3, 44)
extrude "Pointer mark (1)" add sketch "Pointer mark" along normal blind 0.2 separate body makes body 9 in component "REF Select knob"
ref_plane "WorkPlane1" through (0, 0, -16) normal (0, 0, 1) x (1, 0, 0) in component "REF Zoom knob"
sketch "Purchased knob envelope (2)" plane through (0, 0, -16) normal (0, 0, 1) x (1, 0, 0) in component "REF Zoom knob"
  circle A0 centre (99, 36) radius 11
extrude "Purchased knob envelope (1)'" add sketch "Purchased knob envelope (2)" along normal blind 13 separate body makes body 10 in component "REF Zoom knob"
ref_plane "WorkPlane2" through (0, 0, -16.1) normal (0, 0, 1) x (1, 0, 0) in component "REF Zoom knob"
sketch "Pointer mark (2)" plane through (0, 0, -16.1) normal (0, 0, 1) x (1, 0, 0) in component "REF Zoom knob"
  line L0 (98.3, 44) -> (99.7, 44)
  line L1 (99.7, 44) -> (99.7, 46.5)
  line L2 (99.7, 46.5) -> (98.3, 46.5)
  line L3 (98.3, 46.5) -> (98.3, 44)
extrude "Pointer mark (1)'" add sketch "Pointer mark (2)" along normal blind 0.2 separate body makes body 11 in component "REF Zoom knob"
ref_plane "WorkPlane1" through (0, 0, -2) normal (0, 0, 1) x (1, 0, 0) in component "REF HOLD toggle"
sketch "Toggle washer" plane through (0, 0, -2) normal (0, 0, 1) x (1, 0, 0) in component "REF HOLD toggle"
  circle A0 centre (18, 70) radius 4
extrude "Toggle washer (1)" add sketch "Toggle washer" along normal blind 2 separate body makes body 12 in component "REF HOLD toggle"
ref_plane "WorkPlane2" through (0, 0, -15) normal (0, 0, 1) x (1, 0, 0) in component "REF HOLD toggle"
sketch "Metal toggle lever envelope" plane through (0, 0, -15) normal (0, 0, 1) x (1, 0, 0) in component "REF HOLD toggle"
  circle A0 centre (18, 70) radius 1.5
extrude "Metal toggle lever envelope (1)" add sketch "Metal toggle lever envelope" along normal blind 13 separate body makes body 13 in component "REF HOLD toggle"
ref_plane "WorkPlane1" through (0, 0, -2) normal (0, 0, 1) x (1, 0, 0) in component "REF GRID toggle"
sketch "Toggle washer (2)" plane through (0, 0, -2) normal (0, 0, 1) x (1, 0, 0) in component "REF GRID toggle"
  circle A0 centre (117, 70) radius 4
extrude "Toggle washer (1)'" add sketch "Toggle washer (2)" along normal blind 2 separate body makes body 14 in component "REF GRID toggle"
ref_plane "WorkPlane2" through (0, 0, -15) normal (0, 0, 1) x (1, 0, 0) in component "REF GRID toggle"
sketch "Metal toggle lever envelope (2)" plane through (0, 0, -15) normal (0, 0, 1) x (1, 0, 0) in component "REF GRID toggle"
  circle A0 centre (117, 70) radius 1.5
extrude "Metal toggle lever envelope (1)'" add sketch "Metal toggle lever envelope (2)" along normal blind 13 separate body makes body 15 in component "REF GRID toggle"
ref_plane "WorkPlane1" through (0, 0, 5) normal (0, 0, 1) x (1, 0, 0) in component "REF Waveshare module 76.54 x 74.66 - thickness provisional"